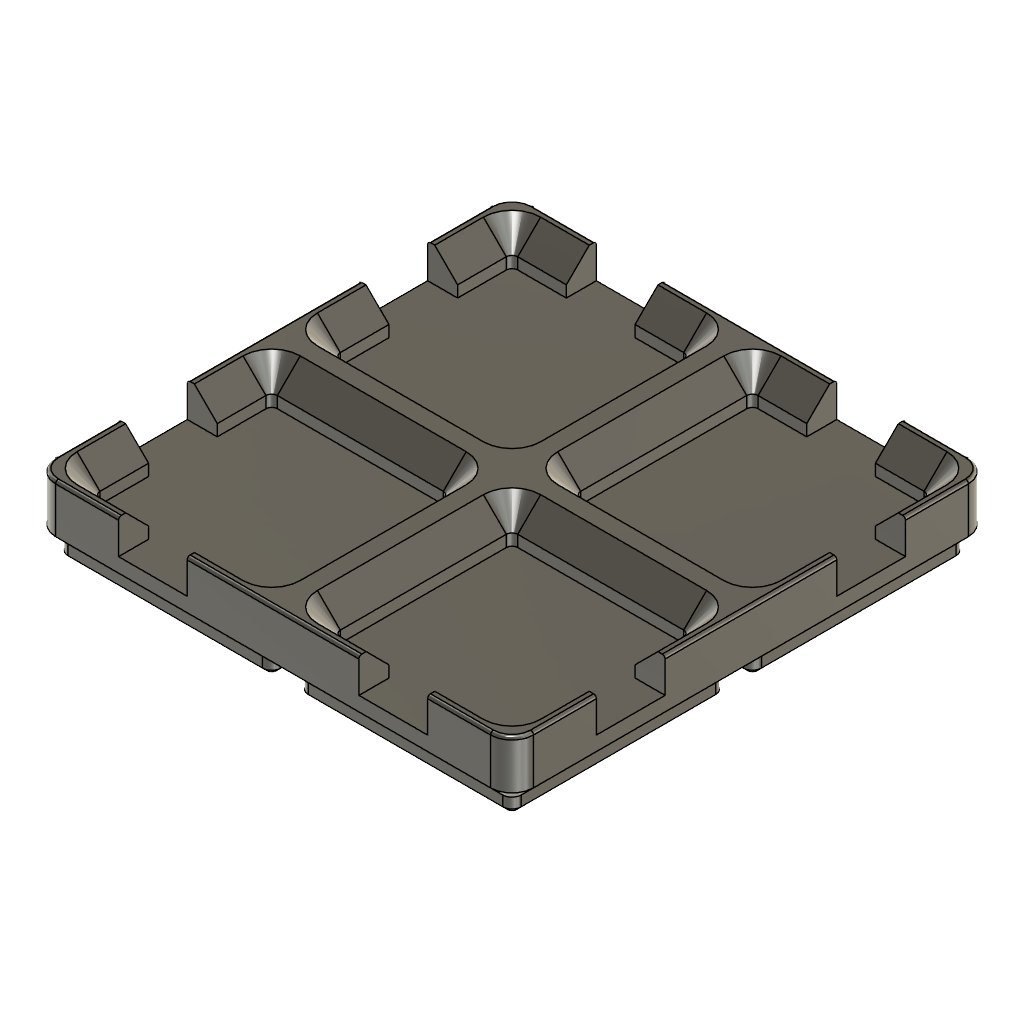
valjundhoidik-v2 (Autodesk Fusion 360 design; units mm, degrees)
part number: 2026-10-03-11-57-42-661
Autodesk Fusion 360 part; units mm, degrees
sketch "Sketch_OuterProfile" plane through (0, 0, 0) normal (0, 0, 1) x (1, 0, 0)
  line L0 (41.75, 41.75) -> (-41.75, 41.75)
  line L1 (-41.75, 41.75) -> (-41.75, -41.75)
  line L2 (-41.75, -41.75) -> (41.75, -41.75)
  line L3 (41.75, -41.75) -> (41.75, 41.75)
  line L4 (41.75, 41.75) -> (-41.75, -41.75) construction
  dimension "d26" = 83.5
  dimension "d27" = 83.5
  constraint midpoint origin L4
  measures "d26" horizontal distance of L0.start L0.end
  measures "d27" vertical distance of L0.end L1.end
extrude "Extrude_Body" add sketch "Sketch_OuterProfile" along normal blind 8.5
fillet "Fillet_OuterVerticalEdges" radius 3.75 4 edges at (41.75, -41.75, 4.25) (-41.75, -41.75, 4.25) (-41.75, 41.75, 4.25) (41.75, 41.75, 4.25)
fillet "Fillet_TopOuterEdge" radius 0.5 64 edges at (40.6517, 40.6517, 8.5) (41.75, 0, 8.5) (40.6517, -40.6517, 8.5) (0, -41.75, 8.5) (-40.6517, -40.6517, 8.5) (-41.75, 0, 8.5) (-40.6517, 40.6517, 8.5) (0, 41.75, 8.5) (0, 41.75, 8.5) (-40.6517, 40.6517, 8.5) (-41.75, 0, 8.5) (-40.6517, -40.6517, 8.5) (0, -41.75, 8.5) (40.6517, -40.6517, 8.5) (41.75, 0, 8.5) (40.6517, 40.6517, 8.5) (-40.6517, 40.6517, 8.5) (0, 41.75, 8.5) (40.6517, 40.6517, 8.5) (41.75, 0, 8.5) (40.6517, -40.6517, 8.5) (0, -41.75, 8.5) (-40.6517, -40.6517, 8.5) (-41.75, 0, 8.5) (-41.75, 0, 8.5) (-40.6517, -40.6517, 8.5) (0, -41.75, 8.5) (40.6517, -40.6517, 8.5) (41.75, 0, 8.5) (40.6517, 40.6517, 8.5) (0, 41.75, 8.5) (-40.6517, 40.6517, 8.5) (-40.6517, -40.6517, 8.5) (-41.75, 0, 8.5) (-40.6517, 40.6517, 8.5) (0, 41.75, 8.5) (40.6517, 40.6517, 8.5) (41.75, 0, 8.5) (40.6517, -40.6517, 8.5) (0, -41.75, 8.5) (0, -41.75, 8.5) (40.6517, -40.6517, 8.5) (41.75, 0, 8.5) (40.6517, 40.6517, 8.5) (0, 41.75, 8.5) (-40.6517, 40.6517, 8.5) (-41.75, 0, 8.5) (-40.6517, -40.6517, 8.5) (40.6517, -40.6517, 8.5) (0, -41.75, 8.5) (-40.6517, -40.6517, 8.5) (-41.75, 0, 8.5) (-40.6517, 40.6517, 8.5) (0, 41.75, 8.5) (40.6517, 40.6517, 8.5) (41.75, 0, 8.5) (41.75, 0, 8.5) (40.6517, 40.6517, 8.5) (0, 41.75, 8.5) (-40.6517, 40.6517, 8.5) (-41.75, 0, 8.5) (-40.6517, -40.6517, 8.5) (0, -41.75, 8.5) (40.6517, -40.6517, 8.5)
ref_plane "WorkPlane1" through (0, 0, 8.5) normal (0, 0, 1) x (1, 0, 0)
sketch "Sketch_Pocket_1" plane through (0, 0, 8.5) normal (0, 0, 1) x (1, 0, 0)
  line L0 (-5.7, -5.7) -> (-36.3, -5.7)
  line L1 (-36.3, -5.7) -> (-36.3, -36.3)
  line L2 (-36.3, -36.3) -> (-5.7, -36.3)
  line L3 (-5.7, -36.3) -> (-5.7, -5.7)
  dimension "d37" = 30.6
  dimension "d38" = 30.6
  measures "d37" horizontal distance of L0.start L0.end
  measures "d38" vertical distance of L0.end L1.end
extrude "Extrude_Pocket_1" [suppressed]
sketch "Sketch_FingerAccessX_1" plane through (0, 0, 8.5) normal (0, 0, 1) x (1, 0, 0)
  circle A0 centre (-36.3, -21) radius 6
extrude "Extrude_FingerAccessX_1" [suppressed]
sketch "Sketch_FingerAccessY_1" plane through (0, 0, 8.5) normal (0, 0, 1) x (1, 0, 0)
  circle A0 centre (-21, -36.3) radius 6
extrude "Extrude_FingerAccessY_1" [suppressed]
sketch "Sketch_Pocket_2" plane through (0, 0, 8.5) normal (0, 0, 1) x (1, 0, 0)
  line L0 (-5.7, 36.3) -> (-36.3, 36.3)
  line L1 (-36.3, 36.3) -> (-36.3, 5.7)
  line L2 (-36.3, 5.7) -> (-5.7, 5.7)
  line L3 (-5.7, 5.7) -> (-5.7, 36.3)
  dimension "d45" = 30.6
  dimension "d46" = 30.6
  measures "d45" horizontal distance of L0.start L0.end
  measures "d46" vertical distance of L0.end L1.end
extrude "Extrude_Pocket_2" [suppressed]
sketch "Sketch_FingerAccessX_2" plane through (0, 0, 8.5) normal (0, 0, 1) x (1, 0, 0)
  circle A0 centre (-36.3, 21) radius 6
extrude "Extrude_FingerAccessX_2" [suppressed]
sketch "Sketch_FingerAccessY_2" plane through (0, 0, 8.5) normal (0, 0, 1) x (1, 0, 0)
  circle A0 centre (-21, 36.3) radius 6
extrude "Extrude_FingerAccessY_2" [suppressed]
sketch "Sketch_Pocket_3" plane through (0, 0, 8.5) normal (0, 0, 1) x (1, 0, 0)
  line L0 (36.3, -5.7) -> (5.7, -5.7)
  line L1 (5.7, -5.7) -> (5.7, -36.3)
  line L2 (5.7, -36.3) -> (36.3, -36.3)
  line L3 (36.3, -36.3) -> (36.3, -5.7)
  dimension "d53" = 30.6
  dimension "d54" = 30.6
  measures "d53" horizontal distance of L0.start L0.end
  measures "d54" vertical distance of L0.end L1.end
extrude "Extrude_Pocket_3" [suppressed]
sketch "Sketch_FingerAccessX_3" plane through (0, 0, 8.5) normal (0, 0, 1) x (1, 0, 0)
  circle A0 centre (36.3, -21) radius 6
extrude "Extrude_FingerAccessX_3" [suppressed]
sketch "Sketch_FingerAccessY_3" plane through (0, 0, 8.5) normal (0, 0, 1) x (1, 0, 0)
  circle A0 centre (21, -36.3) radius 6
extrude "Extrude_FingerAccessY_3" [suppressed]
sketch "Sketch_Pocket_4" plane through (0, 0, 8.5) normal (0, 0, 1) x (1, 0, 0)
  line L0 (36.3, 36.3) -> (5.7, 36.3)
  line L1 (5.7, 36.3) -> (5.7, 5.7)
  line L2 (5.7, 5.7) -> (36.3, 5.7)
  line L3 (36.3, 5.7) -> (36.3, 36.3)
  dimension "d61" = 30.6
  dimension "d62" = 30.6
  measures "d61" horizontal distance of L0.start L0.end
  measures "d62" vertical distance of L0.end L1.end
extrude "Extrude_Pocket_4" [suppressed]
sketch "Sketch_FingerAccessX_4" plane through (0, 0, 8.5) normal (0, 0, 1) x (1, 0, 0)
  circle A0 centre (36.3, 21) radius 6
extrude "Extrude_FingerAccessX_4" [suppressed]
sketch "Sketch_FingerAccessY_4" plane through (0, 0, 8.5) normal (0, 0, 1) x (1, 0, 0)
  circle A0 centre (21, 36.3) radius 6
extrude "Extrude_FingerAccessY_4" [suppressed]
sketch "Sketch_Foot_1" plane through (0, 0, 0) normal (0, 0, 1) x (1, 0, 0)
  line L0 (-3.01, -3.01) -> (-38.79, -3.01)
  line L1 (-38.79, -3.01) -> (-38.79, -38.79)
  line L2 (-38.79, -38.79) -> (-3.01, -38.79)
  line L3 (-3.01, -38.79) -> (-3.01, -3.01)
  dimension "d77" = 35.78
  dimension "d78" = 35.78
  measures "d77" horizontal distance of L0.start L0.end
  measures "d78" vertical distance of L0.end L1.end
extrude "Extrude_Foot_1" [suppressed]
fillet "Fillet_FootEdges_1" [suppressed]
sketch "Sketch_Foot_2" plane through (0, 0, 0) normal (0, 0, 1) x (1, 0, 0)
  line L0 (-3.01, 38.99) -> (-38.79, 38.99)
  line L1 (-38.79, 38.99) -> (-38.79, 3.21)
  line L2 (-38.79, 3.21) -> (-3.01, 3.21)
  line L3 (-3.01, 3.21) -> (-3.01, 38.99)
  dimension "d83" = 35.78
  dimension "d84" = 35.78
  measures "d83" horizontal distance of L0.start L0.end
  measures "d84" vertical distance of L0.end L1.end
extrude "Extrude_Foot_2" [suppressed]
fillet "Fillet_FootEdges_2" [suppressed]
sketch "Sketch_Foot_3" plane through (0, 0, 0) normal (0, 0, 1) x (1, 0, 0)
  line L0 (38.99, -3.01) -> (3.21, -3.01)
  line L1 (3.21, -3.01) -> (3.21, -38.79)
  line L2 (3.21, -38.79) -> (38.99, -38.79)
  line L3 (38.99, -38.79) -> (38.99, -3.01)
  dimension "d89" = 35.78
  dimension "d90" = 35.78
  measures "d89" horizontal distance of L0.start L0.end
  measures "d90" vertical distance of L0.end L1.end
extrude "Extrude_Foot_3" [suppressed]
fillet "Fillet_FootEdges_3" [suppressed]
sketch "Sketch_Foot_4" plane through (0, 0, 0) normal (0, 0, 1) x (1, 0, 0)
  line L0 (38.99, 38.99) -> (3.21, 38.99)
  line L1 (3.21, 38.99) -> (3.21, 3.21)
  line L2 (3.21, 3.21) -> (38.99, 3.21)
  line L3 (38.99, 3.21) -> (38.99, 38.99)
  dimension "d95" = 35.78
  dimension "d96" = 35.78
  measures "d95" horizontal distance of L0.start L0.end
  measures "d96" vertical distance of L0.end L1.end
extrude "Extrude_Foot_4" [suppressed]
fillet "Fillet_FootEdges_4" [suppressed]
extrude "Extrude18" [suppressed]
sketch "Sketch_OutputCavity" plane through (0, 0, 0) normal (0, 0, 1) x (1, 0, 0)
  line L0 (-39.25, -39.25) -> (39.25, -39.25)
  line L1 (39.25, -39.25) -> (39.25, 39.25)
  line L2 (39.25, 39.25) -> (-39.25, 39.25)
  line L3 (-39.25, 39.25) -> (-39.25, -39.25)
  dimension "d115" = 39.25
  dimension "d116" = 39.25
  dimension "d117" = 39.25
  dimension "d118" = 39.25
  measures "d115" horizontal distance of origin L1.end
  measures "d116" vertical distance of origin L1.end
  measures "d117" horizontal distance of origin L0.start
  measures "d118" vertical distance of origin L0.start
extrude "Extrude_OutputCavity" [suppressed]
fillet "Fillet_OutputCavityCorners" [suppressed]
chamfer "Chamfer_OutputLeadIn" [suppressed]
chamfer "Chamfer_FootBottom" [suppressed]
ref_plane "WorkPlane2" through (0, 0, 0) normal (0, 0, 1) x (1, 0, 0)
sketch "gf_std_foot1" plane through (0, 0, 0) normal (0, 0, 1) x (1, 0, 0)
  line L0 (-4, -0.25) -> (-38, -0.25)
  line L1 (-41.75, -4) -> (-41.75, -38)
  line L2 (-38, -41.75) -> (-4, -41.75)
  line L3 (-0.25, -38) -> (-0.25, -4)
  arc A0 (-38, -0.25) -> (-41.75, -4) centre (-38, -4) ccw
  arc A1 (-41.75, -38) -> (-38, -41.75) centre (-38, -38) ccw
  arc A2 (-4, -41.75) -> (-0.25, -38) centre (-4, -38) ccw
  arc A3 (-0.25, -4) -> (-4, -0.25) centre (-4, -4) ccw
  line L4 (-4, 41.75) -> (-38, 41.75)
  line L5 (-41.75, 38) -> (-41.75, 4)
  line L6 (-38, 0.25) -> (-4, 0.25)
  line L7 (-0.25, 4) -> (-0.25, 38)
  arc A4 (-38, 41.75) -> (-41.75, 38) centre (-38, 38) ccw
  arc A5 (-41.75, 4) -> (-38, 0.25) centre (-38, 4) ccw
  arc A6 (-4, 0.25) -> (-0.25, 4) centre (-4, 4) ccw
  arc A7 (-0.25, 38) -> (-4, 41.75) centre (-4, 38) ccw
  line L8 (38, -0.25) -> (4, -0.25)
  line L9 (0.25, -4) -> (0.25, -38)
  line L10 (4, -41.75) -> (38, -41.75)
  line L11 (41.75, -38) -> (41.75, -4)
  arc A8 (4, -0.25) -> (0.25, -4) centre (4, -4) ccw
  arc A9 (0.25, -38) -> (4, -41.75) centre (4, -38) ccw
  arc A10 (38, -41.75) -> (41.75, -38) centre (38, -38) ccw
  arc A11 (41.75, -4) -> (38, -0.25) centre (38, -4) ccw
  line L12 (38, 41.75) -> (4, 41.75)
  line L13 (0.25, 38) -> (0.25, 4)
  line L14 (4, 0.25) -> (38, 0.25)
  line L15 (41.75, 4) -> (41.75, 38)
  arc A12 (4, 41.75) -> (0.25, 38) centre (4, 38) ccw
  arc A13 (0.25, 4) -> (4, 0.25) centre (4, 4) ccw
  arc A14 (38, 0.25) -> (41.75, 4) centre (38, 4) ccw
  arc A15 (41.75, 38) -> (38, 41.75) centre (38, 38) ccw
  constraint tangent L0 A0
  constraint tangent L1 A0
  constraint tangent L1 A1
  constraint tangent L2 A1
  constraint tangent L2 A2
  constraint tangent L3 A2
  constraint tangent L3 A3
  constraint tangent L0 A3
  constraint tangent L4 A4
  constraint tangent L5 A4
  constraint tangent L5 A5
  constraint tangent L6 A5
  constraint tangent L6 A6
  constraint tangent L7 A6
  constraint tangent L7 A7
  constraint tangent L4 A7
  constraint tangent L8 A8
  constraint tangent L9 A8
  constraint tangent L9 A9
  constraint tangent L10 A9
  constraint tangent L10 A10
  constraint tangent L11 A10
  constraint tangent L11 A11
  constraint tangent L8 A11
  constraint tangent L12 A12
  constraint tangent L13 A12
  constraint tangent L13 A13
  constraint tangent L14 A13
  constraint tangent L14 A14
  constraint tangent L15 A14
  constraint tangent L15 A15
  constraint tangent L12 A15
extrude "gf_std_foot1 (1)" add sketch "gf_std_foot1" against normal blind 2.15 draft -45
ref_plane "WorkPlane3" through (0, 0, -2.15) normal (0, 0, 1) x (1, 0, 0)
sketch "gf_std_foot2" plane through (0, 0, -2.15) normal (0, 0, 1) x (1, 0, 0)
  line L0 (-4, -2.4) -> (-38, -2.4)
  line L1 (-39.6, -4) -> (-39.6, -38)
  line L2 (-38, -39.6) -> (-4, -39.6)
  line L3 (-2.4, -38) -> (-2.4, -4)
  arc A0 (-38, -2.4) -> (-39.6, -4) centre (-38, -4) ccw
  arc A1 (-39.6, -38) -> (-38, -39.6) centre (-38, -38) ccw
  arc A2 (-4, -39.6) -> (-2.4, -38) centre (-4, -38) ccw
  arc A3 (-2.4, -4) -> (-4, -2.4) centre (-4, -4) ccw
  line L4 (-4, 39.6) -> (-38, 39.6)
  line L5 (-39.6, 38) -> (-39.6, 4)
  line L6 (-38, 2.4) -> (-4, 2.4)
  line L7 (-2.4, 4) -> (-2.4, 38)
  arc A4 (-38, 39.6) -> (-39.6, 38) centre (-38, 38) ccw
  arc A5 (-39.6, 4) -> (-38, 2.4) centre (-38, 4) ccw
  arc A6 (-4, 2.4) -> (-2.4, 4) centre (-4, 4) ccw
  arc A7 (-2.4, 38) -> (-4, 39.6) centre (-4, 38) ccw
  line L8 (38, -2.4) -> (4, -2.4)
  line L9 (2.4, -4) -> (2.4, -38)
  line L10 (4, -39.6) -> (38, -39.6)
  line L11 (39.6, -38) -> (39.6, -4)
  arc A8 (4, -2.4) -> (2.4, -4) centre (4, -4) ccw
  arc A9 (2.4, -38) -> (4, -39.6) centre (4, -38) ccw
  arc A10 (38, -39.6) -> (39.6, -38) centre (38, -38) ccw
  arc A11 (39.6, -4) -> (38, -2.4) centre (38, -4) ccw
  line L12 (38, 39.6) -> (4, 39.6)
  line L13 (2.4, 38) -> (2.4, 4)
  line L14 (4, 2.4) -> (38, 2.4)
  line L15 (39.6, 4) -> (39.6, 38)
  arc A12 (4, 39.6) -> (2.4, 38) centre (4, 38) ccw
  arc A13 (2.4, 4) -> (4, 2.4) centre (4, 4) ccw
  arc A14 (38, 2.4) -> (39.6, 4) centre (38, 4) ccw
  arc A15 (39.6, 38) -> (38, 39.6) centre (38, 38) ccw
  constraint tangent L0 A0
  constraint tangent L1 A0
  constraint tangent L1 A1
  constraint tangent L2 A1
  constraint tangent L2 A2
  constraint tangent L3 A2
  constraint tangent L3 A3
  constraint tangent L0 A3
  constraint tangent L4 A4
  constraint tangent L5 A4
  constraint tangent L5 A5
  constraint tangent L6 A5
  constraint tangent L6 A6
  constraint tangent L7 A6
  constraint tangent L7 A7
  constraint tangent L4 A7
  constraint tangent L8 A8
  constraint tangent L9 A8
  constraint tangent L9 A9
  constraint tangent L10 A9
  constraint tangent L10 A10
  constraint tangent L11 A10
  constraint tangent L11 A11
  constraint tangent L8 A11
  constraint tangent L12 A12
  constraint tangent L13 A12
  constraint tangent L13 A13
  constraint tangent L14 A13
  constraint tangent L14 A14
  constraint tangent L15 A14
  constraint tangent L15 A15
  constraint tangent L12 A15
extrude "gf_std_foot2 (1)" add sketch "gf_std_foot2" against normal blind 1.8
ref_plane "WorkPlane4" through (0, 0, -3.95) normal (0, 0, 1) x (1, 0, 0)
sketch "gf_std_foot3" plane through (0, 0, -3.95) normal (0, 0, 1) x (1, 0, 0)
  line L0 (-4, -2.4) -> (-38, -2.4)
  line L1 (-39.6, -4) -> (-39.6, -38)
  line L2 (-38, -39.6) -> (-4, -39.6)
  line L3 (-2.4, -38) -> (-2.4, -4)
  arc A0 (-38, -2.4) -> (-39.6, -4) centre (-38, -4) ccw
  arc A1 (-39.6, -38) -> (-38, -39.6) centre (-38, -38) ccw
  arc A2 (-4, -39.6) -> (-2.4, -38) centre (-4, -38) ccw
  arc A3 (-2.4, -4) -> (-4, -2.4) centre (-4, -4) ccw
  line L4 (-4, 39.6) -> (-38, 39.6)
  line L5 (-39.6, 38) -> (-39.6, 4)
  line L6 (-38, 2.4) -> (-4, 2.4)
  line L7 (-2.4, 4) -> (-2.4, 38)
  arc A4 (-38, 39.6) -> (-39.6, 38) centre (-38, 38) ccw
  arc A5 (-39.6, 4) -> (-38, 2.4) centre (-38, 4) ccw
  arc A6 (-4, 2.4) -> (-2.4, 4) centre (-4, 4) ccw
  arc A7 (-2.4, 38) -> (-4, 39.6) centre (-4, 38) ccw
  line L8 (38, -2.4) -> (4, -2.4)
  line L9 (2.4, -4) -> (2.4, -38)
  line L10 (4, -39.6) -> (38, -39.6)
  line L11 (39.6, -38) -> (39.6, -4)
  arc A8 (4, -2.4) -> (2.4, -4) centre (4, -4) ccw
  arc A9 (2.4, -38) -> (4, -39.6) centre (4, -38) ccw
  arc A10 (38, -39.6) -> (39.6, -38) centre (38, -38) ccw
  arc A11 (39.6, -4) -> (38, -2.4) centre (38, -4) ccw
  line L12 (38, 39.6) -> (4, 39.6)
  line L13 (2.4, 38) -> (2.4, 4)
  line L14 (4, 2.4) -> (38, 2.4)
  line L15 (39.6, 4) -> (39.6, 38)
  arc A12 (4, 39.6) -> (2.4, 38) centre (4, 38) ccw
  arc A13 (2.4, 4) -> (4, 2.4) centre (4, 4) ccw
  arc A14 (38, 2.4) -> (39.6, 4) centre (38, 4) ccw
  arc A15 (39.6, 38) -> (38, 39.6) centre (38, 38) ccw
  constraint tangent L0 A0
  constraint tangent L1 A0
  constraint tangent L1 A1
  constraint tangent L2 A1
  constraint tangent L2 A2
  constraint tangent L3 A2
  constraint tangent L3 A3
  constraint tangent L0 A3
  constraint tangent L4 A4
  constraint tangent L5 A4
  constraint tangent L5 A5
  constraint tangent L6 A5
  constraint tangent L6 A6
  constraint tangent L7 A6
  constraint tangent L7 A7
  constraint tangent L4 A7
  constraint tangent L8 A8
  constraint tangent L9 A8
  constraint tangent L9 A9
  constraint tangent L10 A9
  constraint tangent L10 A10
  constraint tangent L11 A10
  constraint tangent L11 A11
  constraint tangent L8 A11
  constraint tangent L12 A12
  constraint tangent L13 A12
  constraint tangent L13 A13
  constraint tangent L14 A13
  constraint tangent L14 A14
  constraint tangent L15 A14
  constraint tangent L15 A15
  constraint tangent L12 A15
extrude "gf_std_foot3 (1)" add sketch "gf_std_foot3" against normal blind 0.8 draft -45
ref_plane "WorkPlane6" through (0, 0, 8.5) normal (0, 0, 1) x (1, 0, 0)
sketch "Sketch_OutputPockets" plane through (0, 0, 8.5) normal (0, 0, 1) x (1, 0, 0)
  line L0 (-5.5, -5.5) -> (-36.5, -5.5)
  line L1 (-36.5, -5.5) -> (-36.5, -36.5)
  line L2 (-36.5, -36.5) -> (-5.5, -36.5)
  line L3 (-5.5, -36.5) -> (-5.5, -5.5)
  line L4 (-5.5, 36.5) -> (-36.5, 36.5)
  line L5 (-36.5, 36.5) -> (-36.5, 5.5)
  line L6 (-36.5, 5.5) -> (-5.5, 5.5)
  line L7 (-5.5, 5.5) -> (-5.5, 36.5)
  line L8 (36.5, -5.5) -> (5.5, -5.5)
  line L9 (5.5, -5.5) -> (5.5, -36.5)
  line L10 (5.5, -36.5) -> (36.5, -36.5)
  line L11 (36.5, -36.5) -> (36.5, -5.5)
  line L12 (36.5, 36.5) -> (5.5, 36.5)
  line L13 (5.5, 36.5) -> (5.5, 5.5)
  line L14 (5.5, 5.5) -> (36.5, 5.5)
  line L15 (36.5, 5.5) -> (36.5, 36.5)
extrude "Extrude_OutputPockets" cut sketch "Sketch_OutputPockets" along normal mid plane 12
fillet "Fillet_OutputPocketCorners" radius 1 16 edges at (5.5, -5.5, 5.5) (36.5, -5.5, 5.5) (36.5, -36.5, 5.5) (5.5, -36.5, 5.5) (-36.5, 36.5, 5.5) (-5.5, 36.5, 5.5) (-5.5, 5.5, 5.5) (-36.5, 5.5, 5.5) (-36.5, -5.5, 5.5) (-5.5, -5.5, 5.5) (-5.5, -36.5, 5.5) (-36.5, -36.5, 5.5) (5.5, 36.5, 5.5) (36.5, 36.5, 5.5) (36.5, 5.5, 5.5) (5.5, 5.5, 5.5)
chamfer "Chamfer_OutputPocketLeadIn" distance 4 angle 45 32 edges at (5.7929, 5.7929, 8.5) (21, 5.5, 8.5) (36.2071, 5.7929, 8.5) (36.5, 21, 8.5) (36.2071, 36.2071, 8.5) (21, 36.5, 8.5) (5.7929, 36.2071, 8.5) (5.5, 21, 8.5) (-36.2071, -36.2071, 8.5) (-21, -36.5, 8.5) (-5.7929, -36.2071, 8.5) (-5.5, -21, 8.5) (-5.7929, -5.7929, 8.5) (-21, -5.5, 8.5) (-36.2071, -5.7929, 8.5) (-36.5, -21, 8.5) (-36.2071, 5.7929, 8.5) (-21, 5.5, 8.5) (-5.7929, 5.7929, 8.5) (-5.5, 21, 8.5) (-5.7929, 36.2071, 8.5) (-21, 36.5, 8.5) (-36.2071, 36.2071, 8.5) (-36.5, 21, 8.5) (5.7929, -36.2071, 8.5) (21, -36.5, 8.5) (36.2071, -36.2071, 8.5) (36.5, -21, 8.5) (36.2071, -5.7929, 8.5) (21, -5.5, 8.5) (5.7929, -5.7929, 8.5) (5.5, -21, 8.5) tangent chain off
ref_plane "WorkPlane7" through (0, 0, 2.5) normal (0, 0, 1) x (1, 0, 0)
sketch "Sketch_FingerSlots" plane through (0, 0, 2.5) normal (0, 0, 1) x (1, 0, 0)
  line L0 (-35.5, -27) -> (-45, -27)
  line L1 (-45, -27) -> (-45, -15)
  line L2 (-45, -15) -> (-35.5, -15)
  line L3 (-35.5, -15) -> (-35.5, -27)
  line L4 (-27, -35.5) -> (-15, -35.5)
  line L5 (-15, -35.5) -> (-15, -45)
  line L6 (-15, -45) -> (-27, -45)
  line L7 (-27, -45) -> (-27, -35.5)
  line L8 (-35.5, 15) -> (-45, 15)
  line L9 (-45, 15) -> (-45, 27)
  line L10 (-45, 27) -> (-35.5, 27)
  line L11 (-35.5, 27) -> (-35.5, 15)
  line L12 (-27, 35.5) -> (-15, 35.5)
  line L13 (-15, 35.5) -> (-15, 45)
  line L14 (-15, 45) -> (-27, 45)
  line L15 (-27, 45) -> (-27, 35.5)
  line L16 (35.5, -27) -> (45, -27)
  line L17 (45, -27) -> (45, -15)
  line L18 (45, -15) -> (35.5, -15)
  line L19 (35.5, -15) -> (35.5, -27)
  line L20 (15, -35.5) -> (27, -35.5)
  line L21 (27, -35.5) -> (27, -45)
  line L22 (27, -45) -> (15, -45)
  line L23 (15, -45) -> (15, -35.5)
  line L24 (35.5, 15) -> (45, 15)
  line L25 (45, 15) -> (45, 27)
  line L26 (45, 27) -> (35.5, 27)
  line L27 (35.5, 27) -> (35.5, 15)
  line L28 (15, 35.5) -> (27, 35.5)
  line L29 (27, 35.5) -> (27, 45)
  line L30 (27, 45) -> (15, 45)
  line L31 (15, 45) -> (15, 35.5)
extrude "Extrude_FingerSlots" cut sketch "Sketch_FingerSlots" along normal blind 7
equation "grid_pitch = 42 mm" comment "Gridfinity grid pitch (standard, per MG400 rig doc)"
equation "grid_clearance = 0.3 mm" comment "Fit clearance measured in Lab 1 (range 0.2-0.4 mm, chosen 0.3 mm)"
equation "gf_outer_offset = 0.5 mm" comment "Standard Gridfinity outer undersize per cell (42n - 0.5)"
equation "gf_corner_radius = 3.75 mm" comment "Standard Gridfinity outer vertical corner radius"
equation "gf_foot_chamfer_bottom = 0.8 mm" comment "Gridfinity foot: bottom 45deg segment height (reference)"
equation "gf_foot_vertical = 1.8 mm" comment "Gridfinity foot: vertical segment height (reference)"
equation "gf_foot_chamfer_top = 2.15 mm" comment "Gridfinity foot: top 45deg segment height (reference)"
equation "foot_lead_in_chamfer = gf_foot_chamfer_bottom + gf_foot_chamfer_top" comment "Simplified single lead-in chamfer approximating the Gridfinity foot flare"
equation "grid_cols = 2" comment "Number of Gridfinity cells in X (build-time layout parameter)"
equation "grid_rows = 2" comment "Number of Gridfinity cells in Y (build-time layout parameter)"
equation "glass_width = 30 mm" comment "Polycarbonate glass piece width (given)"
equation "glass_length = 30 mm" comment "Polycarbonate glass piece length (given)"
equation "glass_thickness = 2 mm" comment "Polycarbonate glass piece thickness (given)"
equation "part_clearance = 0.3 mm" comment "Printer fit clearance measured in Lab 1, applied per side between glass and pocket"
equation "pocket_width = glass_width + 2 * part_clearance" comment "Pocket opening width (glass width plus clearance both sides)"
equation "pocket_length = glass_length + 2 * part_clearance" comment "Pocket opening length (glass length plus clearance both sides)"
equation "reveal_height = 0.5 mm" comment "ASSUMPTION: how far the glass protrudes above the holder top surface for suction-cup and finger access"
equation "pocket_depth = glass_thickness - reveal_height" comment "Pocket depth, kept shallow so the glass top stays exposed"
equation "floor_thickness = 4 mm" comment "ASSUMPTION: solid floor thickness beneath the pocket"
equation "holder_height = out_floor_thickness + out_cavity_depth" comment "Height above the foot: floor + pocket depth (v2: four low pockets, was a 14 mm open box)"
equation "holder_outer_x = grid_pitch * grid_cols - gf_outer_offset" comment "Standard Gridfinity outer size 42n - 0.5 (v2; v1 also subtracted grid_clearance -> 83.2)"
equation "holder_outer_y = grid_pitch * grid_rows - gf_outer_offset" comment "Standard Gridfinity outer size 42n - 0.5 (v2; v1 also subtracted grid_clearance -> 83.2)"
equation "lead_in_chamfer = 0.5 mm" comment "ASSUMPTION: small chamfer around each pocket opening to ease glass insertion (reduced size for this thin, shallow tray)"
equation "top_edge_fillet_radius = 0.5 mm" comment "ASSUMPTION: small deburr fillet on the top outer rim (reduced from standard Gridfinity radius since this part is very thin)"
equation "finger_cutout_radius = 6 mm" comment "ASSUMPTION: radius of the finger-access scallop cut into two outward-facing sides of each pocket"
equation "d26 = holder_outer_x"
equation "d27 = holder_outer_y"
equation "d28 = holder_height"
equation "d31 = gf_corner_radius"
equation "d34 = top_edge_fillet_radius"
equation "d35 = holder_height"
equation "d37 = pocket_width"
equation "d38 = pocket_length"
equation "d39 = -pocket_depth"
equation "d41 = -pocket_depth"
equation "d43 = -pocket_depth"
equation "d45 = pocket_width"
equation "d46 = pocket_length"
equation "d47 = -pocket_depth"
equation "d49 = -pocket_depth"
equation "d51 = -pocket_depth"
equation "d53 = pocket_width"
equation "d54 = pocket_length"
equation "d55 = -pocket_depth"
equation "d57 = -pocket_depth"
equation "d59 = -pocket_depth"
equation "d61 = pocket_width"
equation "d62 = pocket_length"
equation "d63 = -pocket_depth"
equation "d65 = -pocket_depth"
equation "d67 = -pocket_depth"
equation "gf_socket_mouth_size = 41.98 mm" comment "v1 straight foot, NOT USED in v2 (suppressed). MEASURED from MG400 rakis grid_pos_0: top opening of real baseplate socket"
equation "gf_socket_mid_size = 37.68 mm" comment "v1 straight foot, NOT USED in v2 (suppressed). MEASURED: socket width after top chamfer segment"
equation "gf_socket_floor_size = 36.28 mm" comment "v1 straight foot, NOT USED in v2 (suppressed). MEASURED: narrowest width at socket floor"
equation "gf_socket_depth = 4.65 mm" comment "v1 straight foot, NOT USED in v2 (suppressed). MEASURED: real socket depth (0.70 + 1.80 + 2.15 mm segments), corrects earlier 4.75 mm assumption"
equation "foot_size = gf_socket_floor_size - 2 * foot_clearance" comment "v1 straight foot, NOT USED in v2 (suppressed). Constant-width foot: narrowest socket width minus clearance on both sides"
equation "foot_depth = gf_socket_depth" comment "v1 straight foot, NOT USED in v2 (suppressed). Foot protrusion depth below the main floor, matches measured socket depth"
equation "foot_corner_radius = gf_socket_floor_corner_radius + 0.36 mm" comment "v1 straight foot, NOT USED in v2 (suppressed). Foot corner radius kept larger than the socket throat radius (1.14 mm), so the corners never touch first (v1 used 0.5 mm and jammed at the corners)"
equation "total_height_with_feet = holder_height + 4.75 mm" comment "Overall height with the standard 4.75 mm Gridfinity foot"
equation "d77 = foot_size"
equation "d78 = foot_size"
equation "d79 = -foot_depth"
equation "d82 = foot_corner_radius"
equation "d83 = foot_size"
equation "d84 = foot_size"
equation "d85 = -foot_depth"
equation "d88 = foot_corner_radius"
equation "d89 = foot_size"
equation "d90 = foot_size"
equation "d91 = -foot_depth"
equation "d94 = foot_corner_radius"
equation "d95 = foot_size"
equation "d96 = foot_size"
equation "d97 = -foot_depth"
equation "d100 = foot_corner_radius"
equation "out_floor_thickness = 2.5 mm" comment "Output box: floor thickness under the open cavity"
equation "out_cavity_depth = glass_thickness + out_lead_in" comment "Output pocket depth: straight part = glass thickness, then the lead-in"
equation "out_wall_thickness = 2.5 mm" comment "Output box: side wall thickness"
equation "out_cavity_corner_radius = 4 mm" comment "Output box: inner vertical corner radius"
equation "out_lead_in = 4 mm" comment "Output pocket: 45deg lead-in at the top; a glass placed up to ~4 mm off centre slides in"
equation "d115 = ( holder_outer_x - 2 * out_wall_thickness ) / 2"
equation "d116 = ( holder_outer_y - 2 * out_wall_thickness ) / 2"
equation "d117 = ( holder_outer_x - 2 * out_wall_thickness ) / 2"
equation "d118 = ( holder_outer_y - 2 * out_wall_thickness ) / 2"
equation "d119 = holder_height"
equation "d120 = -( out_cavity_depth )"
equation "d123 = out_cavity_corner_radius"
equation "d124 = out_lead_in"
equation "gf_socket_floor_corner_radius = 1.14 mm" comment "MEASURED 23.10.26 in MG 400 rakis (grid_pos_0): corner radius of the narrowest socket section (36.28 mm, z +2.63)"
equation "foot_clearance = 0.25 mm" comment "v1 straight foot, NOT USED in v2 (suppressed). Gap per side between foot and the narrowest socket section (was 0.15 mm per side in v1, too tight with first-layer squish)"
equation "foot_bottom_chamfer = 0.5 mm" comment "v1 straight foot, NOT USED in v2 (suppressed). 45deg chamfer on the foot bottom edge: lead-in into the socket and elephant-foot compensation"
equation "d128 = foot_bottom_chamfer"
equation "gf_fit_adjust = 0 mm" comment "Extra inward offset of the standard Gridfinity foot per side (0 = standard)"
equation "finger_slot_w = 12 mm" comment "Finger slot width through the outer wall, on the two outward sides of every pocket"
equation "finger_slot_floor = 0 mm" comment "Slot bottom above the pocket floor (0: the 2 mm glass edge is free to pinch)"
equation "out_pocket_clearance = 0.5 mm" comment "Output pocket: gap per side around the 30 mm glass (bigger than the 0.3 mm input pockets)"
equation "out_pocket_width = glass_width + 2 * out_pocket_clearance" comment "Output pocket straight-wall width"
equation "out_pocket_corner_radius = 1 mm" comment "Output pocket inner vertical corner radius (clears the square glass corner)"
equation "d151 = holder_height"
equation "d153 = out_cavity_depth"
equation "d156 = out_pocket_corner_radius"
equation "d157 = out_lead_in"
named bodies: "valjundhoidik-v2"
